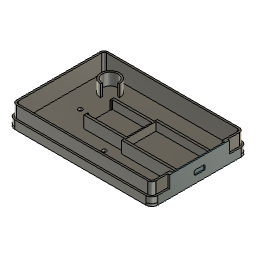
SensorCO2_BackV3 (Autodesk Fusion 360 design; units mm, degrees)
Autodesk Fusion 360 part; units mm, degrees
sketch "Sketch1" plane through (0, 0, 0) normal (0, 0, 1) x (1, 0, 0)
  line L0 (55, -40) -> (-55, -40)
  line L1 (-60, -35) -> (-60, 35)
  line L2 (-55, 40) -> (55, 40)
  line L3 (60, 35) -> (60, -35)
  line L4 (60, -40) -> (-60, 40) construction
  line L5 (-60, -40) -> (60, 40) construction
  arc A0 (-55, 40) -> (-60, 35) centre (-55, 35) ccw
  arc A1 (60, 35) -> (55, 40) centre (55, 35) ccw
  arc A2 (55, -40) -> (60, -35) centre (55, -35) ccw
  arc A3 (-60, -35) -> (-55, -40) centre (-55, -35) ccw
  dimension "d1" = 120
  dimension "d2" = 80
  dimension "d3" = 5
  dimension "d4" = 5
  dimension "d5" = 5
  dimension "d6" = 5
  constraint horizontal L0
  constraint perpendicular L0 L1
  constraint parallel L0 L2
  constraint parallel L1 L3
  constraint coincident L4 origin
  constraint coincident L5 origin
  constraint coincident L4.end L1
  constraint coincident L4.end L2
  constraint tangent L1 A0
  constraint tangent L2 A0
  constraint coincident L5.end L2
  constraint coincident L5.end L3
  constraint tangent L2 A1
  constraint tangent L3 A1
  constraint coincident L4.start L3
  constraint coincident L4.start L0
  constraint tangent L3 A2
  constraint tangent L0 A2
  constraint coincident L5.start L1
  constraint coincident L5.start L0
  constraint tangent L1 A3
  constraint tangent L0 A3
  measures "d1" distance of L4.end L5.end
  measures "d2" distance of L5.start L4.end
  measures "d3" radius of A0
  measures "d4" radius of A1
  measures "d5" radius of A2
  measures "d6" radius of A3
extrude "Extrude1" add sketch "Sketch1" along normal blind 2
sketch "Sketch2" plane through (0, 0, 2) normal (0, 0, 1) x (-1, 0, 0)
  arc A0 (55, -40) -> (60, -35) centre (55, -35) ccw
  line L0 (60, -35) -> (60, 35)
  arc A1 (60, 35) -> (55, 40) centre (55, 35) ccw
  line L1 (55, 40) -> (-55, 40)
  arc A2 (-55, 40) -> (-60, 35) centre (-55, 35) ccw
  line L2 (-60, 35) -> (-60, -35)
  arc A3 (-60, -35) -> (-55, -40) centre (-55, -35) ccw
  line L3 (-55, -40) -> (55, -40)
  line L4 (-55, 40) -> (55, 40)
  line L5 (60, 35) -> (60, -35)
  line L6 (55, -40) -> (-55, -40)
  line L7 (-60, -35) -> (-60, 35)
  line L8 (-60, 40) -> (60, -40) construction
  line L9 (60, 40) -> (-60, -40) construction
  arc A4 (55, -40) -> (60, -35) centre (55, -35) ccw
  arc A5 (-60, -35) -> (-55, -40) centre (-55, -35) ccw
  arc A6 (60, 35) -> (55, 40) centre (55, 35) ccw
  arc A7 (-55, 40) -> (-60, 35) centre (-55, 35) ccw
  arc A8 (-57, -35) -> (-55, -37) centre (-55, -35) ccw
  line L10 (55, -37) -> (-55, -37)
  arc A9 (55, -37) -> (57, -35) centre (55, -35) ccw
  line L11 (57, 35) -> (57, -35)
  arc A10 (57, 35) -> (55, 37) centre (55, 35) ccw
  line L12 (-55, 37) -> (55, 37)
  arc A11 (-55, 37) -> (-57, 35) centre (-55, 35) ccw
  line L13 (-57, -35) -> (-57, 35)
  dimension "d9" = 5
  dimension "d10" = 5
  dimension "d11" = 5
  dimension "d12" = 5
  dimension "d13" = 3
  constraint horizontal L4
  constraint perpendicular L4 L5
  constraint parallel L4 L6
  constraint parallel L5 L7
  constraint coincident L8 origin
  constraint coincident L9 origin
  constraint coincident L8.end L6
  constraint coincident L8.end L5
  constraint tangent L6 A4
  constraint tangent L5 A4
  constraint coincident L9.end L6
  constraint coincident L9.end L7
  constraint tangent L6 A5
  constraint tangent L7 A5
  constraint coincident L9.start L5
  constraint coincident L9.start L4
  constraint tangent L5 A6
  constraint tangent L4 A6
  constraint coincident L8.start L7
  constraint coincident L8.start L4
  constraint tangent L7 A7
  constraint tangent L4 A7
  measures "d9" radius of A4
  measures "d10" radius of A5
  measures "d11" radius of A6
  measures "d12" radius of A7
extrude "Extrude2" add sketch "Sketch2" along normal blind 15
sketch "Sketch3" plane through (0, 0, 17) normal (0, 0, 1) x (-1, 0, 0)
  arc A0 (55, -37) -> (57, -35) centre (55, -35) ccw
  line L0 (55, -37) -> (-55, -37)
  arc A1 (-57, -35) -> (-55, -37) centre (-55, -35) ccw
  line L1 (-57, -35) -> (-57, 35)
  arc A2 (-55, 37) -> (-57, 35) centre (-55, 35) ccw
  line L2 (-55, 37) -> (55, 37)
  arc A3 (57, 35) -> (55, 37) centre (55, 35) ccw
  line L3 (57, 35) -> (57, -35)
  arc A4 (60, 35) -> (55, 40) centre (55, 35) ccw
  line L4 (55, 40) -> (-55, 40)
  arc A5 (-55, 40) -> (-60, 35) centre (-55, 35) ccw
  line L5 (-60, 35) -> (-60, -35)
  arc A6 (-60, -35) -> (-55, -40) centre (-55, -35) ccw
  line L6 (-55, -40) -> (55, -40)
  arc A7 (55, -40) -> (60, -35) centre (55, -35) ccw
  line L7 (60, -35) -> (60, 35)
  line L8 (-55, 40) -> (55, 40)
  line L9 (60, 35) -> (60, -35)
  line L10 (55, -40) -> (-55, -40)
  line L11 (-60, 40) -> (60, -40) construction
  line L12 (60, 40) -> (-60, -40) construction
  arc A8 (55, -40) -> (60, -35) centre (55, -35) ccw
  arc A9 (-60, -35) -> (-55, -40) centre (-55, -35) ccw
  arc A10 (60, 35) -> (55, 40) centre (55, 35) ccw
  arc A11 (-55, 40) -> (-60, 35) centre (-55, 35) ccw
  arc A12 (-58.5, -35) -> (-55, -38.5) centre (-55, -35) ccw
  line L13 (55, -38.5) -> (-55, -38.5)
  arc A13 (55, -38.5) -> (58.5, -35) centre (55, -35) ccw
  line L14 (58.5, 35) -> (58.5, -35)
  arc A14 (58.5, 35) -> (55, 38.5) centre (55, 35) ccw
  line L15 (-55, 38.5) -> (55, 38.5)
  arc A15 (-55, 38.5) -> (-58.5, 35) centre (-55, 35) ccw
  line L16 (-58.5, -25.1477) -> (-60, -25.1477)
  line L17 (-58.5, 25.0695) -> (-60, 25.0695)
  line L18 (-60, -35) -> (-60, -25.1477)
  line L19 (-60, 25.0695) -> (-60, 35)
  line L20 (-58.5, -35) -> (-58.5, -25.1477)
  line L21 (-58.5, 25.0695) -> (-58.5, 35)
  dimension "d16" = 5
  dimension "d17" = 5
  dimension "d18" = 5
  dimension "d19" = 5
  constraint horizontal L8
  constraint perpendicular L8 L9
  constraint parallel L8 L10
  constraint parallel L9 L18
  constraint coincident L11 origin
  constraint coincident L12 origin
  constraint coincident L11.end L10
  constraint coincident L11.end L9
  constraint tangent L10 A8
  constraint tangent L9 A8
  constraint coincident L12.end L10
  constraint coincident L12.end L18
  constraint tangent L10 A9
  constraint tangent A9 L18
  constraint coincident L12.start L9
  constraint coincident L12.start L8
  constraint tangent L9 A10
  constraint tangent L8 A10
  constraint coincident L11.start L8
  constraint coincident L11.start L18
  constraint tangent L8 A11
  constraint tangent A11 L18
  constraint coincident L5 L16.end
  constraint perpendicular L5 L16
  constraint coincident L17.start L20
  constraint coincident L17.end L18
  constraint perpendicular L17 L18
  constraint collinear L18 L19
  constraint concentric A9 A12
  constraint parallel L10 L13
  constraint concentric A8 A13
  constraint parallel L9 L14
  constraint concentric A10 A14
  constraint parallel L8 L15
  constraint concentric A11 A15
  constraint tangent L15 A15
  constraint tangent L14 A14
  constraint tangent A12 L20
  constraint tangent A13 L14
  constraint tangent A15 L20
  constraint tangent A12 L13
  constraint tangent A14 L15
  constraint tangent L13 A13
  constraint collinear L20 L21
  measures "d16" radius of A8
  measures "d17" radius of A9
  measures "d18" radius of A10
  measures "d19" radius of A11
extrude "Extrude3" cut sketch "Sketch3" against normal blind 10 contours A4 L4 A5 L5 A6 L6 A7 L7 L8 L9 L10 A8 A9 A10 A11 A12 L13 A13 L14 A14 L15 A15 L16 L17 L18 L19 L20 L21
sketch "Sketch4" plane through (0, 0, 17) normal (0, 0, 1) x (-1, 0, 0)
  line L0 (-60, -25.1477) -> (-58.5, -25.1477)
  line L1 (-58.5, -25.1477) -> (-58.5, -35)
  arc A0 (-58.5, -35) -> (-55, -38.5) centre (-55, -35) ccw
  line L2 (-55, -38.5) -> (55, -38.5)
  arc A1 (55, -38.5) -> (58.5, -35) centre (55, -35) ccw
  line L3 (58.5, -35) -> (58.5, 35)
  arc A2 (58.5, 35) -> (55, 38.5) centre (55, 35) ccw
  line L4 (55, 38.5) -> (-55, 38.5)
  arc A3 (-55, 38.5) -> (-58.5, 35) centre (-55, 35) ccw
  line L5 (-58.5, 35) -> (-58.5, 25.0695)
  line L6 (-58.5, 25.0695) -> (-60, 25.0695)
  line L7 (-60, 25.0695) -> (-60, -25.1477)
  arc A4 (55, -37) -> (57, -35) centre (55, -35) ccw
  line L8 (55, -37) -> (-55, -37)
  arc A5 (-57, -35) -> (-55, -37) centre (-55, -35) ccw
  line L9 (-57, -35) -> (-57, 35)
  arc A6 (-55, 37) -> (-57, 35) centre (-55, 35) ccw
  line L10 (-55, 37) -> (55, 37)
  arc A7 (57, 35) -> (55, 37) centre (55, 35) ccw
  line L11 (57, 35) -> (57, -35)
  line L12 (-57, -22.0358) -> (-59, -22.0358)
  line L13 (-59, -22.0358) -> (-59, 22)
  line L14 (-59, 22) -> (-57, 22)
  line L15 (-57, 22) -> (-57, -22.0358)
  constraint horizontal L12
  constraint vertical L13
  constraint horizontal L14
  constraint vertical L15
  constraint coincident L9 L12.start
extrude "Extrude4" cut sketch "Sketch4" against normal blind 15 contours L9 L12 L13 L14 L15
sketch "Sketch7" plane through (59, 0, 0) normal (-1, 0, 0) x (0, -1, 0)
  line L0 (22, 2) -> (22, 17)
  line L1 (22, 17) -> (-22.0358, 17)
  line L2 (-22.0358, 17) -> (-22.0358, 2)
  line L3 (-22.0358, 2) -> (22, 2)
sketch "Sketch8" plane through (60, 0, 0) normal (1, 0, 0) x (0, 1, 0)
  line L0 (25.1477, 7) -> (25.1477, 17)
  line L1 (25.1477, 17) -> (-25.0695, 17)
  line L2 (-25.0695, 17) -> (-25.0695, 7)
  line L3 (-25.0695, 7) -> (-35, 7)
  line L4 (-35, 7) -> (-35, 2)
  line L5 (-35, 2) -> (-35, 0)
  line L6 (-35, 0) -> (35, 0)
  line L7 (35, 0) -> (35, 2)
  line L8 (35, 2) -> (35, 7)
  line L9 (35, 7) -> (25.1477, 7)
sketch "Sketch9" plane through (60, 0, 8.5) normal (1, 0, 0) x (0, 1, 0)
  line L0 (-5.492, 8.4032) -> (-5.492, -3.5968) construction
  line L1 (-5.492, -3.5968) -> (13, -3.5968) construction
  line L2 (0.0364, -3.5968) -> (0.0364, -0.5968) construction
  line L3 (3.5364, 1.4032) -> (-3.4636, 1.4032)
  line L4 (-4.4636, 0.4032) -> (-4.4636, -1.5968)
  line L5 (-3.4636, -2.5968) -> (3.5364, -2.5968)
  line L6 (4.5364, -1.5968) -> (4.5364, 0.4032)
  line L7 (4.5364, 1.4032) -> (-4.4636, -2.5968) construction
  line L8 (-4.4636, 1.4032) -> (4.5364, -2.5968) construction
  arc A0 (-3.4636, 1.4032) -> (-4.4636, 0.4032) centre (-3.4636, 0.4032) ccw
  arc A1 (4.5364, 0.4032) -> (3.5364, 1.4032) centre (3.5364, 0.4032) ccw
  arc A2 (3.5364, -2.5968) -> (4.5364, -1.5968) centre (3.5364, -1.5968) ccw
  arc A3 (-4.4636, -1.5968) -> (-3.4636, -2.5968) centre (-3.4636, -1.5968) ccw
  point P0 (0.0364, -0.5968)
  dimension "d37" = 12
  dimension "d38" = 3
  dimension "d39" = 9
  dimension "d40" = 4
  dimension "d41" = 1
  dimension "d42" = 1
  dimension "d43" = 1
  dimension "d44" = 1
  constraint vertical L0
  constraint perpendicular L0 L1
  constraint coincident L1 L2.start
  constraint perpendicular L1 L2
  constraint horizontal L3
  constraint perpendicular L3 L4
  constraint parallel L3 L5
  constraint parallel L4 L6
  constraint coincident L7 P0
  constraint coincident L8 P0
  constraint coincident P0 L2.end
  constraint coincident L8.start L3
  constraint coincident L8.start L4
  constraint tangent L3 A0
  constraint tangent L4 A0
  constraint coincident L7.start L6
  constraint coincident L7.start L3
  constraint tangent L6 A1
  constraint tangent L3 A1
  constraint coincident L8.end L6
  constraint coincident L8.end L5
  constraint tangent L6 A2
  constraint tangent L5 A2
  constraint coincident L7.end L5
  constraint coincident L7.end L4
  constraint tangent L5 A3
  constraint tangent L4 A3
  measures "d37" distance of L0.start L0.end
  measures "d38" distance of L2.start P0
  measures "d39" distance of L7.end L8.end
  measures "d40" distance of L8.start L7.end
  measures "d41" radius of A0
  measures "d42" radius of A1
  measures "d43" radius of A2
  measures "d44" radius of A3
extrude "Extrude7" cut sketch "Sketch9" against normal blind 22
sketch "Sketch10" plane through (0, 0, 2) normal (0, 0, 1) x (-1, 0, 0)
  line L0 (-59, 22) -> (-59, -22.0358)
  line L1 (-59, -22.0358) -> (-57, -22.0358)
  line L2 (-57, -22.0358) -> (-57, -35)
  arc A0 (-57, -35) -> (-55, -37) centre (-55, -35) ccw
  line L3 (-55, -37) -> (55, -37)
  arc A1 (55, -37) -> (57, -35) centre (55, -35) ccw
  line L4 (57, -35) -> (57, 35)
  arc A2 (57, 35) -> (55, 37) centre (55, 35) ccw
  line L5 (55, 37) -> (-55, 37)
  arc A3 (-55, 37) -> (-57, 35) centre (-55, 35) ccw
  line L6 (-57, 35) -> (-57, 22)
  line L7 (-57, 22) -> (-59, 22)
  line L8 (-13.5, 10.5) -> (-8.5, 10.5) construction
  line L9 (-57.5, 10.5) -> (-52.5, 10.5) construction
  line L10 (-8.5, 10.5) -> (-8.5, 13) construction
  line L11 (-52.5, 10.5) -> (-52.5, 8) construction
  circle A4 centre (-8.5, 13) radius 0.75
  circle A5 centre (-52.5, 8) radius 0.75
  line L12 (-8.5, 13) -> (19.5, 13) construction
  line L13 (-52.5, 8) -> (-24.5, 8) construction
  circle A6 centre (19.5, 13) radius 0.75
  circle A7 centre (-24.5, 8) radius 0.75
  dimension "d47" = 5
  dimension "d48" = 5
  dimension "d49" = 2.5
  dimension "d50" = 2.5
  dimension "d51" = 1.5
  dimension "d52" = 1.5
  dimension "d53" = 28
  dimension "d54" = 28
  dimension "d55" = 1.5
  dimension "d56" = 1.5
  constraint horizontal L8
  constraint horizontal L9
  constraint perpendicular L8 L10
  constraint perpendicular L9 L11
  constraint coincident L10.end A4.centre
  constraint coincident L11.end A5.centre
  constraint perpendicular L10 L12
  constraint perpendicular L11 L13
  constraint coincident L12.end A6.centre
  constraint coincident L13.end A7.centre
  measures "d47" distance of L8.start L8.end
  measures "d48" distance of L9.start L9.end
  measures "d49" distance of L8.end L10.end
  measures "d50" distance of L9.end L11.end
  measures "d51" diameter of A4
  measures "d52" diameter of A5
  measures "d53" distance of L10.end L12.end
  measures "d54" distance of L11.end L13.end
  measures "d55" diameter of A6
  measures "d56" diameter of A7
sketch "Sketch13" plane through (0, 0, 2) normal (0, 0, 1) x (-1, 0, 0)
  line L0 (-59, 22) -> (-59, -22.0358)
  line L1 (-59, -22.0358) -> (-57, -22.0358)
  line L2 (-57, -22.0358) -> (-57, -35)
  arc A0 (-57, -35) -> (-55, -37) centre (-55, -35) ccw
  line L3 (-55, -37) -> (55, -37)
  arc A1 (55, -37) -> (57, -35) centre (55, -35) ccw
  line L4 (57, -35) -> (57, 35)
  arc A2 (57, 35) -> (55, 37) centre (55, 35) ccw
  line L5 (55, 37) -> (-55, 37)
  arc A3 (-55, 37) -> (-57, 35) centre (-55, 35) ccw
  line L6 (-57, 35) -> (-57, 22)
  line L7 (-57, 22) -> (-59, 22)
  circle A4 centre (0, -20) radius 1.75
  circle A5 centre (0, 20) radius 1.75
  circle A6 centre (40, 0) radius 1.75
  dimension "d71" = 3.5
  dimension "d72" = 3.5
  dimension "d73" = 3.5
  measures "d71" diameter of A4
  measures "d72" diameter of A5
  measures "d73" diameter of A6
extrude "Extrude11" cut sketch "Sketch13" against normal blind 15 contours A4 | A5 | A6
sketch "Sketch14" plane through (0, 0, 2) normal (0, 0, 1) x (-1, 0, 0)
  circle A0 centre (0, -20) radius 1.75
  circle A1 centre (40, 0) radius 1.75
  circle A2 centre (0, 20) radius 1.75
  line L0 (57, -35) -> (57, 35)
  arc A3 (57, 35) -> (55, 37) centre (55, 35) ccw
  line L1 (55, 37) -> (-55, 37)
  arc A4 (-55, 37) -> (-57, 35) centre (-55, 35) ccw
  line L2 (-57, 35) -> (-57, 22)
  line L3 (-57, 22) -> (-59, 22)
  line L4 (-59, 22) -> (-59, -22.0358)
  line L5 (-59, -22.0358) -> (-57, -22.0358)
  line L6 (-57, -22.0358) -> (-57, -35)
  arc A5 (-57, -35) -> (-55, -37) centre (-55, -35) ccw
  line L7 (-55, -37) -> (55, -37)
  arc A6 (55, -37) -> (57, -35) centre (55, -35) ccw
  line L8 (-59, -0.0179) -> (-59, -13.0179)
  line L9 (-58, 0) -> (-58, -13) construction
  line L10 (-58, 0) -> (-58, 13) construction
  line L11 (-59, -13.0179) -> (-10.5, -13.0179) construction
  line L12 (-59, 13) -> (-10.5, 13) construction
  line L13 (-59, 13) -> (-10.5, 13)
  line L14 (-10.5, -13.0179) -> (-59, -13.0179)
  line L15 (-10.5, -15.0179) -> (-59, -15.0179)
  line L16 (-59, 15) -> (-10.5, 15)
  line L17 (-9.5, -15) -> (-10.5, -15.0179)
  line L18 (-59, -13.0179) -> (-59, -15.0179)
  line L19 (-59, 13) -> (-59, 15)
  line L20 (-9.5, 15) -> (-10.5, 15)
  line L21 (-10.5, -13.0179) -> (-10.5, 13)
  line L22 (-7.0796, -37) -> (-7.0796, -10.5) construction
  line L23 (-7.0315, 37) -> (-7.0315, 10.5) construction
  line L24 (-9.5, -10.489) -> (23.5, -10.489)
  line L25 (-9.5, 10.4859) -> (23.5, 10.4859)
  line L26 (-9.5, -12.489) -> (23.5, -12.489)
  line L27 (-9.5, 12.4859) -> (23.5, 12.4859)
  line L28 (-9.5, 12.4859) -> (-9.5, 15)
  line L29 (-9.5, -15) -> (-9.5, -12.489)
  line L30 (-9.5, -10.489) -> (-9.5, 10.4859)
  line L31 (23.5, -10.489) -> (23.5, -9.489)
  line L32 (23.5, -9.489) -> (24.5, -9.489)
  line L33 (23.5, -12.489) -> (24.5, -12.489)
  line L34 (24.5, -12.489) -> (24.5, -9.489)
  line L35 (23.5, 12.4859) -> (24.5, 12.4859)
  line L36 (23.5, 10.4859) -> (23.5, 9.4859)
  line L37 (23.5, 9.4859) -> (24.5, 9.4859)
  line L38 (24.5, 12.4859) -> (24.5, 9.4859)
  dimension "d76" = 13
  dimension "d77" = 13
  dimension "d78" = 13
  dimension "d79" = 48.5
  dimension "d80" = 48.5
  dimension "d81" = -2
  dimension "d82" = -2
  dimension "d85" = 26.5
  dimension "d86" = 26.5
  dimension "d87" = 33
  dimension "d89" = 33
  dimension "d90" = 2
  dimension "d91" = -2
  dimension "d92" = 1
  dimension "d93" = 1
  dimension "d94" = 1
  dimension "d95" = 1
  dimension "d96" = 1
  dimension "d97" = 1
  constraint midpoint L4 L8.start
  constraint perpendicular L7 L8
  constraint vertical L9
  constraint parallel L9 L10
  constraint perpendicular L9 L11
  constraint coincident L4 L12.start
  constraint perpendicular L4 L12
  constraint horizontal L13
  constraint horizontal L14
  constraint perpendicular L20 L29
  constraint coincident L7 L22.start
  constraint perpendicular L7 L22
  constraint coincident L1 L23.start
  constraint perpendicular L1 L23
  constraint coincident L24.start L29
  constraint perpendicular L22 L24
  constraint perpendicular L25 L29
  constraint collinear L28 L29
  constraint collinear L29 L30
  constraint perpendicular L24 L31
  constraint perpendicular L31 L32
  constraint parallel L26 L33
  constraint perpendicular L32 L34
  constraint parallel L27 L35
  constraint perpendicular L25 L36
  constraint perpendicular L36 L37
  constraint perpendicular L37 L38
  measures "d76" distance of L8.start L8.end
  measures "d77" distance of L9.start L9.end
  measures "d78" distance of L9.start L10.end
  measures "d79" distance of L8.end L11.end
  measures "d80" distance of L12.start L12.end
  measures "d85" distance of L22.start L22.end
  measures "d86" distance of L23.start L23.end
  measures "d87" distance of L24.start L24.end
  measures "d89" distance of L25.start L25.end
  measures "d92" distance of L24.end L31.end
  measures "d93" distance of L31.end L32.end
  measures "d94" distance of L26.end L33.end
  measures "d95" distance of L27.end L35.end
  measures "d96" distance of L25.end L36.end
  measures "d97" distance of L36.end L37.end
extrude "Extrude12" add sketch "Sketch14" along normal blind 10 contours L4 L13 L14 L15 L16 L17 L18 L19 L20 L21 L24 L25 L26 L27 L28 L29 L30 L31 L32 L33 L34 L35 L36 L37 L38
sketch "Sketch15" plane through (0, 0, 2) normal (0, 0, 1) x (-1, 0, 0)
  line L0 (-10.5, -15.0179) -> (-59, -15.0179)
  line L1 (-59, -15.0179) -> (-59, -22.0358)
  line L2 (-59, -22.0358) -> (-57, -22.0358)
  line L3 (-57, -22.0358) -> (-57, -35)
  arc A0 (-57, -35) -> (-55, -37) centre (-55, -35) ccw
  line L4 (-55, -37) -> (55, -37)
  arc A1 (55, -37) -> (57, -35) centre (55, -35) ccw
  line L5 (57, -35) -> (57, 35)
  arc A2 (57, 35) -> (55, 37) centre (55, 35) ccw
  line L6 (55, 37) -> (-55, 37)
  arc A3 (-55, 37) -> (-57, 35) centre (-55, 35) ccw
  line L7 (-57, 35) -> (-57, 22)
  line L8 (-57, 22) -> (-59, 22)
  line L9 (-59, 22) -> (-59, 15)
  line L10 (-59, 15) -> (-9.5, 15)
  line L11 (-9.5, 15) -> (-9.5, 12.4859)
  line L12 (-9.5, 12.4859) -> (24.5, 12.4859)
  line L13 (24.5, 12.4859) -> (24.5, 9.4859)
  line L14 (24.5, 9.4859) -> (23.5, 9.4859)
  line L15 (23.5, 9.4859) -> (23.5, 10.4859)
  line L16 (23.5, 10.4859) -> (-9.5, 10.4859)
  line L17 (-9.5, 10.4859) -> (-9.5, -10.489)
  line L18 (-9.5, -10.489) -> (23.5, -10.489)
  line L19 (23.5, -10.489) -> (23.5, -9.489)
  line L20 (23.5, -9.489) -> (24.5, -9.489)
  line L21 (24.5, -9.489) -> (24.5, -12.489)
  line L22 (24.5, -12.489) -> (-9.5, -12.489)
  line L23 (-9.5, -12.489) -> (-9.5, -15)
  line L24 (-9.5, -15) -> (-10.5, -15.0179)
  circle A4 centre (0, -20) radius 1.75
  circle A5 centre (40, 0) radius 1.75
  circle A6 centre (0, 20) radius 1.75
  line L25 (-59, -13) -> (-10, -13)
  line L26 (-10, -13) -> (-10, 13)
  line L27 (-10, 13) -> (-59, 13)
  line L28 (-59, 13) -> (-59, -13)
  line L29 (-9.5, -11.2276) -> (23.8723, -11.2276)
  line L30 (23.8723, -11.2276) -> (23.8723, 10.9859)
  line L31 (23.8723, 10.9859) -> (-9.5, 10.9859)
  line L32 (-9.5, 10.9859) -> (-9.5, -11.2276)
  constraint horizontal L25
  constraint vertical L26
  constraint horizontal L27
  constraint vertical L28
  constraint horizontal L29
  constraint vertical L30
  constraint horizontal L31
  constraint vertical L32
extrude "Extrude13" add sketch "Sketch15" along normal blind 3 contours L14 L15 L16 L17 L18 L19 L20 L30 L32 | L25 L26 L27 L28
sketch "Sketch16" plane through (0, 0, 2) normal (0, 0, 1) x (-1, 0, 0)
  line L0 (23.8723, 9.4859) -> (23.8723, -9.489)
  line L1 (23.8723, -9.489) -> (24.5, -9.489)
  line L2 (24.5, -9.489) -> (24.5, -12.489)
  line L3 (24.5, -12.489) -> (-9.5, -12.489)
  line L4 (-9.5, -12.489) -> (-9.5, -15)
  line L5 (-9.5, -15) -> (-10.5, -15.0179)
  line L6 (-10.5, -15.0179) -> (-59, -15.0179)
  line L7 (-59, -15.0179) -> (-59, -22.0358)
  line L8 (-59, -22.0358) -> (-57, -22.0358)
  line L9 (-57, -22.0358) -> (-57, -35)
  arc A0 (-57, -35) -> (-55, -37) centre (-55, -35) ccw
  line L10 (-55, -37) -> (55, -37)
  arc A1 (55, -37) -> (57, -35) centre (55, -35) ccw
  line L11 (57, -35) -> (57, 35)
  arc A2 (57, 35) -> (55, 37) centre (55, 35) ccw
  line L12 (55, 37) -> (-55, 37)
  arc A3 (-55, 37) -> (-57, 35) centre (-55, 35) ccw
  line L13 (-57, 35) -> (-57, 22)
  line L14 (-57, 22) -> (-59, 22)
  line L15 (-59, 22) -> (-59, 15)
  line L16 (-59, 15) -> (-9.5, 15)
  line L17 (-9.5, 15) -> (-9.5, 12.4859)
  line L18 (-9.5, 12.4859) -> (24.5, 12.4859)
  line L19 (24.5, 12.4859) -> (24.5, 9.4859)
  line L20 (24.5, 9.4859) -> (23.8723, 9.4859)
  circle A4 centre (0, -20) radius 1.75
  circle A5 centre (40, 0) radius 1.75
  circle A6 centre (0, 20) radius 1.75
  line L21 (33.5, -25.004) -> (32, -25.004)
  line L22 (39.9405, -18.5003) -> (39.9405, -17.0002)
  arc A7 (33.5, -25.004) -> (39.9405, -18.5003) centre (40, -25) ccw
  arc A8 (32, -25.004) -> (39.9405, -17.0002) centre (40, -25) ccw
  dimension "d102" = 13
  constraint horizontal L21
  constraint vertical L22
  measures "d102" diameter of A7
extrude "Extrude14" add sketch "Sketch16" along normal blind 10 contours L21 L22 A7 A8
